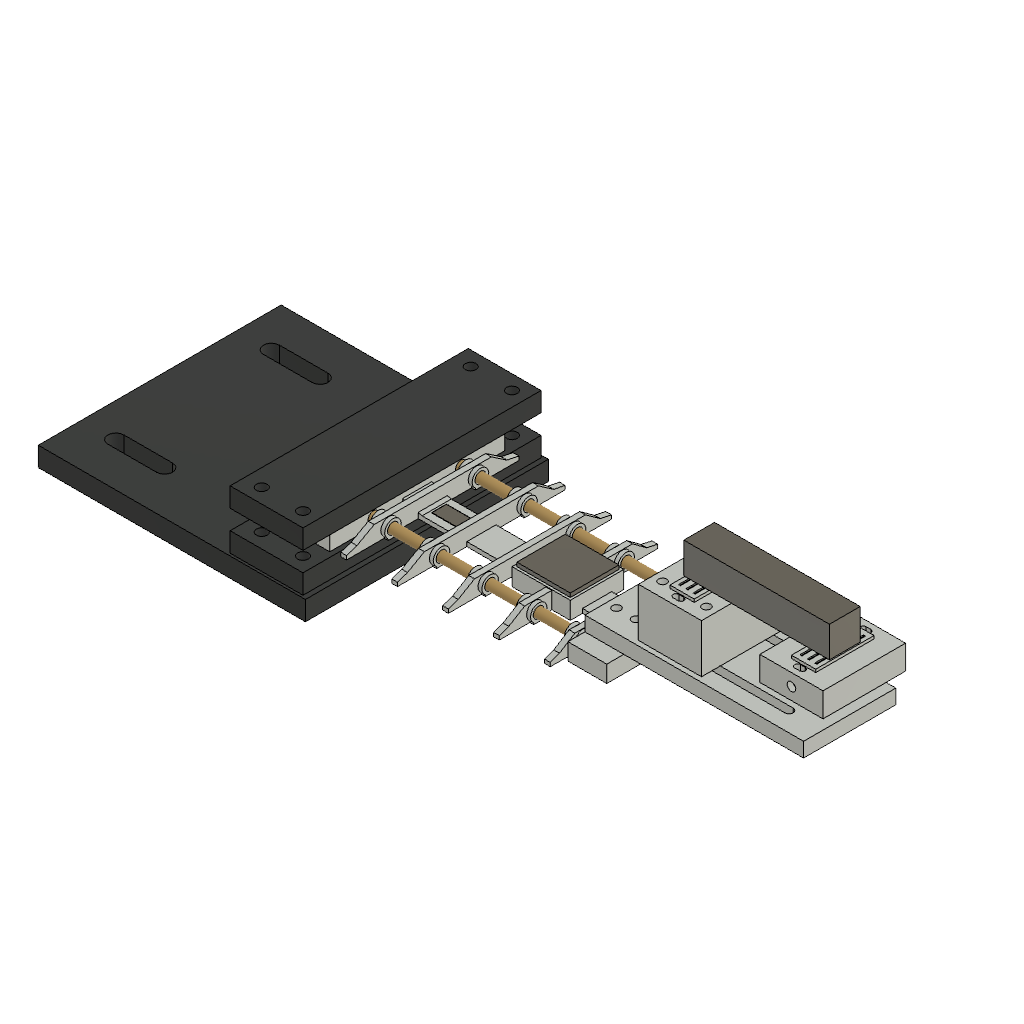
SkySafe_Assembly (Autodesk Fusion 360 design; units mm, degrees)
part number: 2026-10-10-16-37-15-513
part number: 2026-10-10-16-37-16-082
part number: 2026-10-10-16-37-18-375
part number: 2026-10-10-16-37-19-680
part number: 2026-10-10-16-37-20-182
part number: 2026-10-10-16-37-20-972
part number: 2026-10-10-16-37-22-516
part number: 2026-10-10-16-37-23-693
part number: 2026-10-10-16-37-41-112
Autodesk Fusion 360 part; units mm, degrees
(part 1 of 2)
sketch "Root tongue sketch" plane through (0, 0, 0) normal (0, 0, 1) x (1, 0, 0) in component "01 Flexible wing - short 4.5mm spar guides"
  line L0 (0, -36) -> (24, -36)
  line L1 (24, -36) -> (24, 36)
  line L2 (24, 36) -> (0, 36)
  line L3 (0, 36) -> (0, -36)
extrude "Root tongue" add sketch "Root tongue sketch" along normal blind 8 makes body 1 in component "01 Flexible wing - short 4.5mm spar guides"
sketch "Continuous flat flexing gauge strip sketch" plane through (0, 0, 0) normal (0, 0, 1) x (1, 0, 0) in component "01 Flexible wing - short 4.5mm spar guides"
  line L0 (23.95, -6) -> (128, -6)
  line L1 (128, -6) -> (128, 6)
  line L2 (128, 6) -> (23.95, 6)
  line L3 (23.95, 6) -> (23.95, -6)
extrude "Continuous flat flexing gauge strip" add sketch "Continuous flat flexing gauge strip sketch" along normal blind 1.8 bodies 1 in component "01 Flexible wing - short 4.5mm spar guides"
sketch "Root tapered strip shoulder sketch" plane through (0, 0, 0) normal (0, 1, 0) x (1, 0, 0) in component "01 Flexible wing - short 4.5mm spar guides"
  line L0 (23.95, 0) -> (32, 0)
  line L1 (32, 0) -> (32, -1.8)
  line L2 (32, -1.8) -> (23.95, -4)
  line L3 (23.95, -4) -> (23.95, 0)
extrude "Root tapered strip shoulder" add sketch "Root tapered strip shoulder sketch" along normal mid plane 12 bodies 1 in component "01 Flexible wing - short 4.5mm spar guides"
sketch "Tip tapered strip shoulder sketch" plane through (0, 0, 0) normal (0, 1, 0) x (1, 0, 0) in component "01 Flexible wing - short 4.5mm spar guides"
  line L0 (104, 0) -> (112.05, 0)
  line L1 (112.05, 0) -> (112.05, -6.95)
  line L2 (112.05, -6.95) -> (104, -1.8)
  line L3 (104, -1.8) -> (104, 0)
extrude "Tip tapered strip shoulder" add sketch "Tip tapered strip shoulder sketch" along normal mid plane 12 bodies 1 in component "01 Flexible wing - short 4.5mm spar guides"
ref_plane "WorkPlane1" through (28, 0, 0) normal (1, 0, 0) x (0, 1, 0) in component "01 Flexible wing - short 4.5mm spar guides"
sketch "Rib at 28 mm sketch" plane through (28, 0, 0) normal (1, 0, 0) x (0, 0, -1) in component "01 Flexible wing - short 4.5mm spar guides"
  line L0 (0, -35.4923) -> (0, 35.4923)
  line L1 (0, 35.4923) -> (-1.6, 35.4923)
  line L2 (-1.6, 35.4923) -> (-2.6, 30.5234)
  line L3 (-2.6, 30.5234) -> (-6.95, 24.1348)
  line L4 (-6.95, 24.1348) -> (-6.95, -24.1348)
  line L5 (-6.95, -24.1348) -> (-3, -31.2332)
  line L6 (-3, -31.2332) -> (-1.6, -35.4923)
  line L7 (-1.6, -35.4923) -> (0, -35.4923)
extrude "Rib at 28 mm" add sketch "Rib at 28 mm sketch" along normal blind 2.4 bodies 1 in component "01 Flexible wing - short 4.5mm spar guides"
ref_plane "WorkPlane2" through (26, 0, 0) normal (1, 0, 0) x (0, 1, 0) in component "01 Flexible wing - short 4.5mm spar guides"
sketch "front short guide at 28 mm sketch" plane through (26, 0, 0) normal (1, 0, 0) x (0, 0, -1) in component "01 Flexible wing - short 4.5mm spar guides"
  circle A0 centre (-3.4, -18) radius 3.4
extrude "front short guide at 28 mm" add sketch "front short guide at 28 mm sketch" along normal blind 6 bodies 1 in component "01 Flexible wing - short 4.5mm spar guides"
sketch "front guide print foot at 28 mm sketch" plane through (0, 0, 0) normal (0, 0, 1) x (1, 0, 0) in component "01 Flexible wing - short 4.5mm spar guides"
  line L0 (26, -20) -> (32, -20)
  line L1 (32, -20) -> (32, -16)
  line L2 (32, -16) -> (26, -16)
  line L3 (26, -16) -> (26, -20)
extrude "front guide print foot at 28 mm" add sketch "front guide print foot at 28 mm sketch" along normal blind 1.2 bodies 1 in component "01 Flexible wing - short 4.5mm spar guides"
ref_plane "WorkPlane3" through (26, 0, 0) normal (1, 0, 0) x (0, 1, 0) in component "01 Flexible wing - short 4.5mm spar guides"
sketch "rear short guide at 28 mm sketch" plane through (26, 0, 0) normal (1, 0, 0) x (0, 0, -1) in component "01 Flexible wing - short 4.5mm spar guides"
  circle A0 centre (-3.4, 18) radius 3.4
extrude "rear short guide at 28 mm" add sketch "rear short guide at 28 mm sketch" along normal blind 6 bodies 1 in component "01 Flexible wing - short 4.5mm spar guides"
sketch "rear guide print foot at 28 mm sketch" plane through (0, 0, 0) normal (0, 0, 1) x (1, 0, 0) in component "01 Flexible wing - short 4.5mm spar guides"
  line L0 (26, 16) -> (32, 16)
  line L1 (32, 16) -> (32, 20)
  line L2 (32, 20) -> (26, 20)
  line L3 (26, 20) -> (26, 16)
extrude "rear guide print foot at 28 mm" add sketch "rear guide print foot at 28 mm sketch" along normal blind 1.2 bodies 1 in component "01 Flexible wing - short 4.5mm spar guides"
ref_plane "WorkPlane4" through (48, 0, 0) normal (1, 0, 0) x (0, 1, 0) in component "01 Flexible wing - short 4.5mm spar guides"
sketch "Rib at 48 mm sketch" plane through (48, 0, 0) normal (1, 0, 0) x (0, 0, -1) in component "01 Flexible wing - short 4.5mm spar guides"
  line L0 (0, -34.5308) -> (0, 34.5308)
  line L1 (0, 34.5308) -> (-1.6, 34.5308)
  line L2 (-1.6, 34.5308) -> (-2.6, 29.6965)
  line L3 (-2.6, 29.6965) -> (-6.95, 23.4809)
  line L4 (-6.95, 23.4809) -> (-6.95, -23.4809)
  line L5 (-6.95, -23.4809) -> (-3, -30.3871)
  line L6 (-3, -30.3871) -> (-1.6, -34.5308)
  line L7 (-1.6, -34.5308) -> (0, -34.5308)
extrude "Rib at 48 mm" add sketch "Rib at 48 mm sketch" along normal blind 2.4 bodies 1 in component "01 Flexible wing - short 4.5mm spar guides"
ref_plane "WorkPlane5" through (46, 0, 0) normal (1, 0, 0) x (0, 1, 0) in component "01 Flexible wing - short 4.5mm spar guides"
sketch "front short guide at 48 mm sketch" plane through (46, 0, 0) normal (1, 0, 0) x (0, 0, -1) in component "01 Flexible wing - short 4.5mm spar guides"
  circle A0 centre (-3.4, -18) radius 3.4
extrude "front short guide at 48 mm" add sketch "front short guide at 48 mm sketch" along normal blind 6 bodies 1 in component "01 Flexible wing - short 4.5mm spar guides"
sketch "front guide print foot at 48 mm sketch" plane through (0, 0, 0) normal (0, 0, 1) x (1, 0, 0) in component "01 Flexible wing - short 4.5mm spar guides"
  line L0 (46, -20) -> (52, -20)
  line L1 (52, -20) -> (52, -16)
  line L2 (52, -16) -> (46, -16)
  line L3 (46, -16) -> (46, -20)
extrude "front guide print foot at 48 mm" add sketch "front guide print foot at 48 mm sketch" along normal blind 1.2 bodies 1 in component "01 Flexible wing - short 4.5mm spar guides"
ref_plane "WorkPlane6" through (46, 0, 0) normal (1, 0, 0) x (0, 1, 0) in component "01 Flexible wing - short 4.5mm spar guides"
sketch "rear short guide at 48 mm sketch" plane through (46, 0, 0) normal (1, 0, 0) x (0, 0, -1) in component "01 Flexible wing - short 4.5mm spar guides"
  circle A0 centre (-3.4, 18) radius 3.4
extrude "rear short guide at 48 mm" add sketch "rear short guide at 48 mm sketch" along normal blind 6 bodies 1 in component "01 Flexible wing - short 4.5mm spar guides"
sketch "rear guide print foot at 48 mm sketch" plane through (0, 0, 0) normal (0, 0, 1) x (1, 0, 0) in component "01 Flexible wing - short 4.5mm spar guides"
  line L0 (46, 16) -> (52, 16)
  line L1 (52, 16) -> (52, 20)
  line L2 (52, 20) -> (46, 20)
  line L3 (46, 20) -> (46, 16)
extrude "rear guide print foot at 48 mm" add sketch "rear guide print foot at 48 mm sketch" along normal blind 1.2 bodies 1 in component "01 Flexible wing - short 4.5mm spar guides"
ref_plane "WorkPlane7" through (68, 0, 0) normal (1, 0, 0) x (0, 1, 0) in component "01 Flexible wing - short 4.5mm spar guides"
sketch "Rib at 68 mm sketch" plane through (68, 0, 0) normal (1, 0, 0) x (0, 0, -1) in component "01 Flexible wing - short 4.5mm spar guides"
  line L0 (0, -33.5692) -> (0, 33.5692)
  line L1 (0, 33.5692) -> (-1.6, 33.5692)
  line L2 (-1.6, 33.5692) -> (-2.6, 28.8695)
  line L3 (-2.6, 28.8695) -> (-6.95, 22.8271)
  line L4 (-6.95, 22.8271) -> (-6.95, -22.8271)
  line L5 (-6.95, -22.8271) -> (-3, -29.5409)
  line L6 (-3, -29.5409) -> (-1.6, -33.5692)
  line L7 (-1.6, -33.5692) -> (0, -33.5692)
extrude "Rib at 68 mm" add sketch "Rib at 68 mm sketch" along normal blind 2.4 bodies 1 in component "01 Flexible wing - short 4.5mm spar guides"
ref_plane "WorkPlane8" through (66, 0, 0) normal (1, 0, 0) x (0, 1, 0) in component "01 Flexible wing - short 4.5mm spar guides"
sketch "front short guide at 68 mm sketch" plane through (66, 0, 0) normal (1, 0, 0) x (0, 0, -1) in component "01 Flexible wing - short 4.5mm spar guides"
  circle A0 centre (-3.4, -18) radius 3.4
extrude "front short guide at 68 mm" add sketch "front short guide at 68 mm sketch" along normal blind 6 bodies 1 in component "01 Flexible wing - short 4.5mm spar guides"
sketch "front guide print foot at 68 mm sketch" plane through (0, 0, 0) normal (0, 0, 1) x (1, 0, 0) in component "01 Flexible wing - short 4.5mm spar guides"
  line L0 (66, -20) -> (72, -20)
  line L1 (72, -20) -> (72, -16)
  line L2 (72, -16) -> (66, -16)
  line L3 (66, -16) -> (66, -20)
extrude "front guide print foot at 68 mm" add sketch "front guide print foot at 68 mm sketch" along normal blind 1.2 bodies 1 in component "01 Flexible wing - short 4.5mm spar guides"
ref_plane "WorkPlane9" through (66, 0, 0) normal (1, 0, 0) x (0, 1, 0) in component "01 Flexible wing - short 4.5mm spar guides"
sketch "rear short guide at 68 mm sketch" plane through (66, 0, 0) normal (1, 0, 0) x (0, 0, -1) in component "01 Flexible wing - short 4.5mm spar guides"
  circle A0 centre (-3.4, 18) radius 3.4
extrude "rear short guide at 68 mm" add sketch "rear short guide at 68 mm sketch" along normal blind 6 bodies 1 in component "01 Flexible wing - short 4.5mm spar guides"
sketch "rear guide print foot at 68 mm sketch" plane through (0, 0, 0) normal (0, 0, 1) x (1, 0, 0) in component "01 Flexible wing - short 4.5mm spar guides"
  line L0 (66, 16) -> (72, 16)
  line L1 (72, 16) -> (72, 20)
  line L2 (72, 20) -> (66, 20)
  line L3 (66, 20) -> (66, 16)
extrude "rear guide print foot at 68 mm" add sketch "rear guide print foot at 68 mm sketch" along normal blind 1.2 bodies 1 in component "01 Flexible wing - short 4.5mm spar guides"
ref_plane "WorkPlane10" through (88, 0, 0) normal (1, 0, 0) x (0, 1, 0) in component "01 Flexible wing - short 4.5mm spar guides"
sketch "Rib at 88 mm sketch" plane through (88, 0, 0) normal (1, 0, 0) x (0, 0, -1) in component "01 Flexible wing - short 4.5mm spar guides"
  line L0 (0, -32.6077) -> (0, 32.6077)
  line L1 (0, 32.6077) -> (-1.6, 32.6077)
  line L2 (-1.6, 32.6077) -> (-2.6, 28.0426)
  line L3 (-2.6, 28.0426) -> (-6.95, 22.1732)
  line L4 (-6.95, 22.1732) -> (-6.95, -22.1732)
  line L5 (-6.95, -22.1732) -> (-3, -28.6948)
  line L6 (-3, -28.6948) -> (-1.6, -32.6077)
  line L7 (-1.6, -32.6077) -> (0, -32.6077)
extrude "Rib at 88 mm" add sketch "Rib at 88 mm sketch" along normal blind 2.4 bodies 1 in component "01 Flexible wing - short 4.5mm spar guides"
ref_plane "WorkPlane11" through (86, 0, 0) normal (1, 0, 0) x (0, 1, 0) in component "01 Flexible wing - short 4.5mm spar guides"
sketch "front short guide at 88 mm sketch" plane through (86, 0, 0) normal (1, 0, 0) x (0, 0, -1) in component "01 Flexible wing - short 4.5mm spar guides"
  circle A0 centre (-3.4, -18) radius 3.4
extrude "front short guide at 88 mm" add sketch "front short guide at 88 mm sketch" along normal blind 6 bodies 1 in component "01 Flexible wing - short 4.5mm spar guides"
sketch "front guide print foot at 88 mm sketch" plane through (0, 0, 0) normal (0, 0, 1) x (1, 0, 0) in component "01 Flexible wing - short 4.5mm spar guides"
  line L0 (86, -20) -> (92, -20)
  line L1 (92, -20) -> (92, -16)
  line L2 (92, -16) -> (86, -16)
  line L3 (86, -16) -> (86, -20)
extrude "front guide print foot at 88 mm" add sketch "front guide print foot at 88 mm sketch" along normal blind 1.2 bodies 1 in component "01 Flexible wing - short 4.5mm spar guides"
ref_plane "WorkPlane12" through (86, 0, 0) normal (1, 0, 0) x (0, 1, 0) in component "01 Flexible wing - short 4.5mm spar guides"
sketch "rear short guide at 88 mm sketch" plane through (86, 0, 0) normal (1, 0, 0) x (0, 0, -1) in component "01 Flexible wing - short 4.5mm spar guides"
  circle A0 centre (-3.4, 18) radius 3.4
extrude "rear short guide at 88 mm" add sketch "rear short guide at 88 mm sketch" along normal blind 6 bodies 1 in component "01 Flexible wing - short 4.5mm spar guides"
sketch "rear guide print foot at 88 mm sketch" plane through (0, 0, 0) normal (0, 0, 1) x (1, 0, 0) in component "01 Flexible wing - short 4.5mm spar guides"
  line L0 (86, 16) -> (92, 16)
  line L1 (92, 16) -> (92, 20)
  line L2 (92, 20) -> (86, 20)
  line L3 (86, 20) -> (86, 16)
extrude "rear guide print foot at 88 mm" add sketch "rear guide print foot at 88 mm sketch" along normal blind 1.2 bodies 1 in component "01 Flexible wing - short 4.5mm spar guides"
ref_plane "WorkPlane13" through (108, 0, 0) normal (1, 0, 0) x (0, 1, 0) in component "01 Flexible wing - short 4.5mm spar guides"
sketch "Rib at 108 mm sketch" plane through (108, 0, 0) normal (1, 0, 0) x (0, 0, -1) in component "01 Flexible wing - short 4.5mm spar guides"
  line L0 (0, -31.6462) -> (0, 31.6462)
  line L1 (0, 31.6462) -> (-1.6, 31.6462)
  line L2 (-1.6, 31.6462) -> (-2.6, 27.2157)
  line L3 (-2.6, 27.2157) -> (-6.95, 21.5194)
  line L4 (-6.95, 21.5194) -> (-6.95, -21.5194)
  line L5 (-6.95, -21.5194) -> (-3, -27.8486)
  line L6 (-3, -27.8486) -> (-1.6, -31.6462)
  line L7 (-1.6, -31.6462) -> (0, -31.6462)
extrude "Rib at 108 mm" add sketch "Rib at 108 mm sketch" along normal blind 2.4 bodies 1 in component "01 Flexible wing - short 4.5mm spar guides"
ref_plane "WorkPlane14" through (106, 0, 0) normal (1, 0, 0) x (0, 1, 0) in component "01 Flexible wing - short 4.5mm spar guides"
sketch "front short guide at 108 mm sketch" plane through (106, 0, 0) normal (1, 0, 0) x (0, 0, -1) in component "01 Flexible wing - short 4.5mm spar guides"
  circle A0 centre (-3.4, -18) radius 3.4
extrude "front short guide at 108 mm" add sketch "front short guide at 108 mm sketch" along normal blind 6 bodies 1 in component "01 Flexible wing - short 4.5mm spar guides"
sketch "front guide print foot at 108 mm sketch" plane through (0, 0, 0) normal (0, 0, 1) x (1, 0, 0) in component "01 Flexible wing - short 4.5mm spar guides"
  line L0 (106, -20) -> (112, -20)
  line L1 (112, -20) -> (112, -16)
  line L2 (112, -16) -> (106, -16)
  line L3 (106, -16) -> (106, -20)
extrude "front guide print foot at 108 mm" add sketch "front guide print foot at 108 mm sketch" along normal blind 1.2 bodies 1 in component "01 Flexible wing - short 4.5mm spar guides"
ref_plane "WorkPlane15" through (106, 0, 0) normal (1, 0, 0) x (0, 1, 0) in component "01 Flexible wing - short 4.5mm spar guides"
sketch "rear short guide at 108 mm sketch" plane through (106, 0, 0) normal (1, 0, 0) x (0, 0, -1) in component "01 Flexible wing - short 4.5mm spar guides"
  circle A0 centre (-3.4, 18) radius 3.4
extrude "rear short guide at 108 mm" add sketch "rear short guide at 108 mm sketch" along normal blind 6 bodies 1 in component "01 Flexible wing - short 4.5mm spar guides"
sketch "rear guide print foot at 108 mm sketch" plane through (0, 0, 0) normal (0, 0, 1) x (1, 0, 0) in component "01 Flexible wing - short 4.5mm spar guides"
  line L0 (106, 16) -> (112, 16)
  line L1 (112, 16) -> (112, 20)
  line L2 (112, 20) -> (106, 20)
  line L3 (106, 20) -> (106, 16)
extrude "rear guide print foot at 108 mm" add sketch "rear guide print foot at 108 mm sketch" along normal blind 1.2 bodies 1 in component "01 Flexible wing - short 4.5mm spar guides"
sketch "Tip load landing sketch" plane through (0, 0, 0) normal (0, 0, 1) x (1, 0, 0) in component "01 Flexible wing - short 4.5mm spar guides"
  line L0 (112, -26) -> (128, -26)
  line L1 (128, -26) -> (128, 26)
  line L2 (128, 26) -> (112, 26)
  line L3 (112, 26) -> (112, -26)
extrude "Tip load landing" add sketch "Tip load landing sketch" along normal blind 6.95 bodies 1 in component "01 Flexible wing - short 4.5mm spar guides"
sketch "MPU strap landing sketch" plane through (0, 0, 0) normal (0, 0, 1) x (1, 0, 0) in component "01 Flexible wing - short 4.5mm spar guides"
  line L0 (74, -11) -> (98, -11)
  line L1 (98, -11) -> (98, 11)
  line L2 (98, 11) -> (74, 11)
  line L3 (74, 11) -> (74, -11)
extrude "MPU strap landing" add sketch "MPU strap landing sketch" along normal blind 7.2 bodies 1 in component "01 Flexible wing - short 4.5mm spar guides"
ref_plane "WorkPlane16" through (-0.05, 0, 0) normal (1, 0, 0) x (0, 1, 0) in component "01 Flexible wing - short 4.5mm spar guides"
sketch "front 4mm bamboo passage sketch" plane through (-0.05, 0, 0) normal (1, 0, 0) x (0, 0, -1) in component "01 Flexible wing - short 4.5mm spar guides"
  circle A0 centre (-3.4, -18) radius 2.25
  dimension "d103" = 4.5
  measures "d103" diameter of A0
extrude "front 4mm bamboo passage" cut sketch "front 4mm bamboo passage sketch" along normal blind 126.05 bodies 1 in component "01 Flexible wing - short 4.5mm spar guides"
ref_plane "WorkPlane17" through (-0.05, 0, 0) normal (1, 0, 0) x (0, 1, 0) in component "01 Flexible wing - short 4.5mm spar guides"
sketch "rear 4mm bamboo passage sketch" plane through (-0.05, 0, 0) normal (1, 0, 0) x (0, 0, -1) in component "01 Flexible wing - short 4.5mm spar guides"
  circle A0 centre (-3.4, 18) radius 2.25
  dimension "d108" = 4.5
  measures "d108" diameter of A0
extrude "rear 4mm bamboo passage" cut sketch "rear 4mm bamboo passage sketch" along normal blind 126.05 bodies 1 in component "01 Flexible wing - short 4.5mm spar guides"
ref_plane "WorkPlane18" through (0, 0, -0.05) normal (0, 0, 1) x (1, 0, 0) in component "01 Flexible wing - short 4.5mm spar guides"
sketch "Root registration -8 sketch" plane through (0, 0, -0.05) normal (0, 0, 1) x (1, 0, 0) in component "01 Flexible wing - short 4.5mm spar guides"
  circle A0 centre (8, -8) radius 1.7
  dimension "d113" = 3.4
  measures "d113" diameter of A0
extrude "Root registration -8" cut sketch "Root registration -8 sketch" along normal blind 8.1 bodies 1 in component "01 Flexible wing - short 4.5mm spar guides"
ref_plane "WorkPlane19" through (0, 0, -0.05) normal (0, 0, 1) x (1, 0, 0) in component "01 Flexible wing - short 4.5mm spar guides"
sketch "Root registration 8 sketch" plane through (0, 0, -0.05) normal (0, 0, 1) x (1, 0, 0) in component "01 Flexible wing - short 4.5mm spar guides"
  circle A0 centre (8, 8) radius 1.7
  dimension "d118" = 3.4
  measures "d118" diameter of A0
extrude "Root registration 8" cut sketch "Root registration 8 sketch" along normal blind 8.1 bodies 1 in component "01 Flexible wing - short 4.5mm spar guides"
ref_plane "WorkPlane20" through (0, 0, -0.05) normal (0, 0, 1) x (1, 0, 0) in component "01 Flexible wing - short 4.5mm spar guides"
sketch "Tip bolt 116 -10 sketch" plane through (0, 0, -0.05) normal (0, 0, 1) x (1, 0, 0) in component "01 Flexible wing - short 4.5mm spar guides"
  circle A0 centre (116, -10) radius 1.7
  dimension "d123" = 3.4
  measures "d123" diameter of A0
extrude "Tip bolt 116 -10" cut sketch "Tip bolt 116 -10 sketch" along normal blind 7.05 bodies 1 in component "01 Flexible wing - short 4.5mm spar guides"
ref_plane "WorkPlane21" through (0, 0, -0.05) normal (0, 0, 1) x (1, 0, 0) in component "01 Flexible wing - short 4.5mm spar guides"
sketch "Tip bolt 116 10 sketch" plane through (0, 0, -0.05) normal (0, 0, 1) x (1, 0, 0) in component "01 Flexible wing - short 4.5mm spar guides"
  circle A0 centre (116, 10) radius 1.7
  dimension "d128" = 3.4
  measures "d128" diameter of A0
extrude "Tip bolt 116 10" cut sketch "Tip bolt 116 10 sketch" along normal blind 7.05 bodies 1 in component "01 Flexible wing - short 4.5mm spar guides"
ref_plane "WorkPlane22" through (0, 0, -0.05) normal (0, 0, 1) x (1, 0, 0) in component "01 Flexible wing - short 4.5mm spar guides"
sketch "Tip bolt 124 -10 sketch" plane through (0, 0, -0.05) normal (0, 0, 1) x (1, 0, 0) in component "01 Flexible wing - short 4.5mm spar guides"
  circle A0 centre (124, -10) radius 1.7
  dimension "d133" = 3.4
  measures "d133" diameter of A0
extrude "Tip bolt 124 -10" cut sketch "Tip bolt 124 -10 sketch" along normal blind 7.05 bodies 1 in component "01 Flexible wing - short 4.5mm spar guides"
ref_plane "WorkPlane23" through (0, 0, -0.05) normal (0, 0, 1) x (1, 0, 0) in component "01 Flexible wing - short 4.5mm spar guides"
sketch "Tip bolt 124 10 sketch" plane through (0, 0, -0.05) normal (0, 0, 1) x (1, 0, 0) in component "01 Flexible wing - short 4.5mm spar guides"
  circle A0 centre (124, 10) radius 1.7
  dimension "d138" = 3.4
  measures "d138" diameter of A0
extrude "Tip bolt 124 10" cut sketch "Tip bolt 124 10 sketch" along normal blind 7.05 bodies 1 in component "01 Flexible wing - short 4.5mm spar guides"
ref_plane "WorkPlane24" through (0, 0, -0.05) normal (0, 0, 1) x (1, 0, 0) in component "01 Flexible wing - short 4.5mm spar guides"
sketch "Board tie 78 -7 sketch" plane through (0, 0, -0.05) normal (0, 0, 1) x (1, 0, 0) in component "01 Flexible wing - short 4.5mm spar guides"
  arc A0 (77.5, -5.9) -> (77.5, -8.1) centre (77.5, -7) ccw
  line L0 (77.5, -5.9) -> (78.5, -5.9)
  arc A1 (78.5, -8.1) -> (78.5, -5.9) centre (78.5, -7) ccw
  line L1 (78.5, -8.1) -> (77.5, -8.1)
extrude "Board tie 78 -7" cut sketch "Board tie 78 -7 sketch" along normal blind 7.3 bodies 1 in component "01 Flexible wing - short 4.5mm spar guides"
ref_plane "WorkPlane25" through (0, 0, -0.05) normal (0, 0, 1) x (1, 0, 0) in component "01 Flexible wing - short 4.5mm spar guides"
sketch "Board tie 78 7 sketch" plane through (0, 0, -0.05) normal (0, 0, 1) x (1, 0, 0) in component "01 Flexible wing - short 4.5mm spar guides"
  arc A0 (77.5, 8.1) -> (77.5, 5.9) centre (77.5, 7) ccw
  line L0 (77.5, 8.1) -> (78.5, 8.1)
  arc A1 (78.5, 5.9) -> (78.5, 8.1) centre (78.5, 7) ccw
  line L1 (78.5, 5.9) -> (77.5, 5.9)
extrude "Board tie 78 7" cut sketch "Board tie 78 7 sketch" along normal blind 7.3 bodies 1 in component "01 Flexible wing - short 4.5mm spar guides"
ref_plane "WorkPlane26" through (0, 0, -0.05) normal (0, 0, 1) x (1, 0, 0) in component "01 Flexible wing - short 4.5mm spar guides"
sketch "Board tie 94 -7 sketch" plane through (0, 0, -0.05) normal (0, 0, 1) x (1, 0, 0) in component "01 Flexible wing - short 4.5mm spar guides"
  arc A0 (93.5, -5.9) -> (93.5, -8.1) centre (93.5, -7) ccw
  line L0 (93.5, -5.9) -> (94.5, -5.9)
  arc A1 (94.5, -8.1) -> (94.5, -5.9) centre (94.5, -7) ccw
  line L1 (94.5, -8.1) -> (93.5, -8.1)
extrude "Board tie 94 -7" cut sketch "Board tie 94 -7 sketch" along normal blind 7.3 bodies 1 in component "01 Flexible wing - short 4.5mm spar guides"
ref_plane "WorkPlane27" through (0, 0, -0.05) normal (0, 0, 1) x (1, 0, 0) in component "01 Flexible wing - short 4.5mm spar guides"
sketch "Board tie 94 7 sketch" plane through (0, 0, -0.05) normal (0, 0, 1) x (1, 0, 0) in component "01 Flexible wing - short 4.5mm spar guides"
  arc A0 (93.5, 8.1) -> (93.5, 5.9) centre (93.5, 7) ccw
  line L0 (93.5, 8.1) -> (94.5, 8.1)
  arc A1 (94.5, 5.9) -> (94.5, 8.1) centre (94.5, 7) ccw
  line L1 (94.5, 5.9) -> (93.5, 5.9)
extrude "Board tie 94 7" cut sketch "Board tie 94 7 sketch" along normal blind 7.3 bodies 1 in component "01 Flexible wing - short 4.5mm spar guides"
sketch "Bench mounting plate sketch" plane through (0, 0, 0) normal (0, 0, 1) x (1, 0, 0) in component "02 Root base - bench clamp"
  line L0 (-82, -50) -> (28, -50)
  line L1 (28, -50) -> (28, 50)
  line L2 (28, 50) -> (-82, 50)
  line L3 (-82, 50) -> (-82, -50)
extrude "Bench mounting plate" add sketch "Bench mounting plate sketch" along normal blind 8 separate body makes body 2 in component "02 Root base - bench clamp"
ref_plane "WorkPlane1" through (0, 0, 8) normal (0, 0, 1) x (1, 0, 0) in component "02 Root base - bench clamp"
sketch "Lower root jaw sketch" plane through (0, 0, 8) normal (0, 0, 1) x (1, 0, 0) in component "02 Root base - bench clamp"
  line L0 (-4, -49) -> (26, -49)
  line L1 (26, -49) -> (26, 49)
  line L2 (26, 49) -> (-4, 49)
  line L3 (-4, 49) -> (-4, -49)
extrude "Lower root jaw" add sketch "Lower root jaw sketch" along normal blind 8 bodies 2 in component "02 Root base - bench clamp"
ref_plane "WorkPlane2" through (0, 0, 15.95) normal (0, 0, 1) x (1, 0, 0) in component "02 Root base - bench clamp"
sketch "Root pin -8 sketch" plane through (0, 0, 15.95) normal (0, 0, 1) x (1, 0, 0) in component "02 Root base - bench clamp"
  circle A0 centre (8, -8) radius 1.5
extrude "Root pin -8" add sketch "Root pin -8 sketch" along normal blind 2.05 bodies 2 in component "02 Root base - bench clamp"
ref_plane "WorkPlane3" through (0, 0, 15.95) normal (0, 0, 1) x (1, 0, 0) in component "02 Root base - bench clamp"
sketch "Root pin 8 sketch" plane through (0, 0, 15.95) normal (0, 0, 1) x (1, 0, 0) in component "02 Root base - bench clamp"
  circle A0 centre (8, 8) radius 1.5
extrude "Root pin 8" add sketch "Root pin 8 sketch" along normal blind 2.05 bodies 2 in component "02 Root base - bench clamp"
ref_plane "WorkPlane4" through (0, 0, -0.05) normal (0, 0, 1) x (1, 0, 0) in component "02 Root base - bench clamp"
sketch "Jaw bolt 3 -43 sketch" plane through (0, 0, -0.05) normal (0, 0, 1) x (1, 0, 0) in component "02 Root base - bench clamp"
  circle A0 centre (3, -43) radius 2.2
  dimension "d173" = 4.4
  measures "d173" diameter of A0
extrude "Jaw bolt 3 -43" cut sketch "Jaw bolt 3 -43 sketch" along normal blind 16.1 bodies 2 in component "02 Root base - bench clamp"
ref_plane "WorkPlane5" through (0, 0, -0.05) normal (0, 0, 1) x (1, 0, 0) in component "02 Root base - bench clamp"
sketch "Nut pocket 3 -43 sketch" plane through (0, 0, -0.05) normal (0, 0, 1) x (1, 0, 0) in component "02 Root base - bench clamp"
  line L0 (6.55, -40.9504) -> (3, -38.9008)
  line L1 (3, -38.9008) -> (-0.55, -40.9504)
  line L2 (-0.55, -40.9504) -> (-0.55, -45.0496)
  line L3 (-0.55, -45.0496) -> (3, -47.0992)
  line L4 (3, -47.0992) -> (6.55, -45.0496)
  line L5 (6.55, -45.0496) -> (6.55, -40.9504)
extrude "Nut pocket 3 -43" cut sketch "Nut pocket 3 -43 sketch" along normal blind 3.35 bodies 2 in component "02 Root base - bench clamp"
ref_plane "WorkPlane6" through (0, 0, -0.05) normal (0, 0, 1) x (1, 0, 0) in component "02 Root base - bench clamp"
sketch "Jaw bolt 3 43 sketch" plane through (0, 0, -0.05) normal (0, 0, 1) x (1, 0, 0) in component "02 Root base - bench clamp"
  circle A0 centre (3, 43) radius 2.2
  dimension "d182" = 4.4
  measures "d182" diameter of A0
extrude "Jaw bolt 3 43" cut sketch "Jaw bolt 3 43 sketch" along normal blind 16.1 bodies 2 in component "02 Root base - bench clamp"
ref_plane "WorkPlane7" through (0, 0, -0.05) normal (0, 0, 1) x (1, 0, 0) in component "02 Root base - bench clamp"
sketch "Nut pocket 3 43 sketch" plane through (0, 0, -0.05) normal (0, 0, 1) x (1, 0, 0) in component "02 Root base - bench clamp"
  line L0 (6.55, 45.0496) -> (3, 47.0992)
  line L1 (3, 47.0992) -> (-0.55, 45.0496)
  line L2 (-0.55, 45.0496) -> (-0.55, 40.9504)
  line L3 (-0.55, 40.9504) -> (3, 38.9008)
  line L4 (3, 38.9008) -> (6.55, 40.9504)
  line L5 (6.55, 40.9504) -> (6.55, 45.0496)
extrude "Nut pocket 3 43" cut sketch "Nut pocket 3 43 sketch" along normal blind 3.35 bodies 2 in component "02 Root base - bench clamp"
ref_plane "WorkPlane8" through (0, 0, -0.05) normal (0, 0, 1) x (1, 0, 0) in component "02 Root base - bench clamp"
sketch "Jaw bolt 20 -43 sketch" plane through (0, 0, -0.05) normal (0, 0, 1) x (1, 0, 0) in component "02 Root base - bench clamp"
  circle A0 centre (20, -43) radius 2.2
  dimension "d191" = 4.4
  measures "d191" diameter of A0
extrude "Jaw bolt 20 -43" cut sketch "Jaw bolt 20 -43 sketch" along normal blind 16.1 bodies 2 in component "02 Root base - bench clamp"
ref_plane "WorkPlane9" through (0, 0, -0.05) normal (0, 0, 1) x (1, 0, 0) in component "02 Root base - bench clamp"
sketch "Nut pocket 20 -43 sketch" plane through (0, 0, -0.05) normal (0, 0, 1) x (1, 0, 0) in component "02 Root base - bench clamp"
  line L0 (23.55, -40.9504) -> (20, -38.9008)
  line L1 (20, -38.9008) -> (16.45, -40.9504)
  line L2 (16.45, -40.9504) -> (16.45, -45.0496)
  line L3 (16.45, -45.0496) -> (20, -47.0992)
  line L4 (20, -47.0992) -> (23.55, -45.0496)
  line L5 (23.55, -45.0496) -> (23.55, -40.9504)
extrude "Nut pocket 20 -43" cut sketch "Nut pocket 20 -43 sketch" along normal blind 3.35 bodies 2 in component "02 Root base - bench clamp"
ref_plane "WorkPlane10" through (0, 0, -0.05) normal (0, 0, 1) x (1, 0, 0) in component "02 Root base - bench clamp"
sketch "Jaw bolt 20 43 sketch" plane through (0, 0, -0.05) normal (0, 0, 1) x (1, 0, 0) in component "02 Root base - bench clamp"
  circle A0 centre (20, 43) radius 2.2
  dimension "d200" = 4.4
  measures "d200" diameter of A0
extrude "Jaw bolt 20 43" cut sketch "Jaw bolt 20 43 sketch" along normal blind 16.1 bodies 2 in component "02 Root base - bench clamp"
ref_plane "WorkPlane11" through (0, 0, -0.05) normal (0, 0, 1) x (1, 0, 0) in component "02 Root base - bench clamp"
sketch "Nut pocket 20 43 sketch" plane through (0, 0, -0.05) normal (0, 0, 1) x (1, 0, 0) in component "02 Root base - bench clamp"
  line L0 (23.55, 45.0496) -> (20, 47.0992)
  line L1 (20, 47.0992) -> (16.45, 45.0496)
  line L2 (16.45, 45.0496) -> (16.45, 40.9504)
  line L3 (16.45, 40.9504) -> (20, 38.9008)
  line L4 (20, 38.9008) -> (23.55, 40.9504)
  line L5 (23.55, 40.9504) -> (23.55, 45.0496)
extrude "Nut pocket 20 43" cut sketch "Nut pocket 20 43 sketch" along normal blind 3.35 bodies 2 in component "02 Root base - bench clamp"
ref_plane "WorkPlane12" through (0, 0, -0.05) normal (0, 0, 1) x (1, 0, 0) in component "02 Root base - bench clamp"
sketch "Bench slot -32 sketch" plane through (0, 0, -0.05) normal (0, 0, 1) x (1, 0, 0) in component "02 Root base - bench clamp"
  arc A0 (-68, -28.7) -> (-68, -35.3) centre (-68, -32) ccw
  line L0 (-68, -28.7) -> (-48, -28.7)
  arc A1 (-48, -35.3) -> (-48, -28.7) centre (-48, -32) ccw
  line L1 (-48, -35.3) -> (-68, -35.3)
extrude "Bench slot -32" cut sketch "Bench slot -32 sketch" along normal blind 8.1 bodies 2 in component "02 Root base - bench clamp"
ref_plane "WorkPlane13" through (0, 0, -0.05) normal (0, 0, 1) x (1, 0, 0) in component "02 Root base - bench clamp"
sketch "Bench slot 32 sketch" plane through (0, 0, -0.05) normal (0, 0, 1) x (1, 0, 0) in component "02 Root base - bench clamp"
  arc A0 (-68, 35.3) -> (-68, 28.7) centre (-68, 32) ccw
  line L0 (-68, 35.3) -> (-48, 35.3)
  arc A1 (-48, 28.7) -> (-48, 35.3) centre (-48, 32) ccw
  line L1 (-48, 28.7) -> (-68, 28.7)
extrude "Bench slot 32" cut sketch "Bench slot 32 sketch" along normal blind 8.1 bodies 2 in component "02 Root base - bench clamp"
sketch "Upper root jaw sketch" plane through (0, 0, 0) normal (0, 0, 1) x (1, 0, 0) in component "03 Root cap"
  line L0 (-4, -49) -> (26, -49)
  line L1 (26, -49) -> (26, 49)
  line L2 (26, 49) -> (-4, 49)
  line L3 (-4, 49) -> (-4, -49)
extrude "Upper root jaw" add sketch "Upper root jaw sketch" along normal blind 8 separate body makes body 3 in component "03 Root cap"
ref_plane "WorkPlane1" through (0, 0, -0.05) normal (0, 0, 1) x (1, 0, 0) in component "03 Root cap"
sketch "Cap bolt 3 -43 sketch" plane through (0, 0, -0.05) normal (0, 0, 1) x (1, 0, 0) in component "03 Root cap"
  circle A0 centre (3, -43) radius 2.2
  dimension "d219" = 4.4
  measures "d219" diameter of A0
extrude "Cap bolt 3 -43" cut sketch "Cap bolt 3 -43 sketch" along normal blind 8.1 bodies 3 in component "03 Root cap"
ref_plane "WorkPlane2" through (0, 0, -0.05) normal (0, 0, 1) x (1, 0, 0) in component "03 Root cap"
sketch "Cap bolt 3 43 sketch" plane through (0, 0, -0.05) normal (0, 0, 1) x (1, 0, 0) in component "03 Root cap"
  circle A0 centre (3, 43) radius 2.2
  dimension "d224" = 4.4
  measures "d224" diameter of A0
extrude "Cap bolt 3 43" cut sketch "Cap bolt 3 43 sketch" along normal blind 8.1 bodies 3 in component "03 Root cap"
ref_plane "WorkPlane3" through (0, 0, -0.05) normal (0, 0, 1) x (1, 0, 0) in component "03 Root cap"
sketch "Cap bolt 20 -43 sketch" plane through (0, 0, -0.05) normal (0, 0, 1) x (1, 0, 0) in component "03 Root cap"
  circle A0 centre (20, -43) radius 2.2
  dimension "d229" = 4.4
  measures "d229" diameter of A0
extrude "Cap bolt 20 -43" cut sketch "Cap bolt 20 -43 sketch" along normal blind 8.1 bodies 3 in component "03 Root cap"
ref_plane "WorkPlane4" through (0, 0, -0.05) normal (0, 0, 1) x (1, 0, 0) in component "03 Root cap"
sketch "Cap bolt 20 43 sketch" plane through (0, 0, -0.05) normal (0, 0, 1) x (1, 0, 0) in component "03 Root cap"
  circle A0 centre (20, 43) radius 2.2
  dimension "d234" = 4.4
  measures "d234" diameter of A0
extrude "Cap bolt 20 43" cut sketch "Cap bolt 20 43 sketch" along normal blind 8.1 bodies 3 in component "03 Root cap"
sketch "Adapter plate sketch" plane through (0, 0, 0) normal (0, 0, 1) x (1, 0, 0) in component "04 Tip adapter - adjustable glue mount rails"
  line L0 (0, -19) -> (90, -19)
  line L1 (90, -19) -> (90, 19)
  line L2 (90, 19) -> (0, 19)
  line L3 (0, 19) -> (0, -19)
extrude "Adapter plate" add sketch "Adapter plate sketch" along normal blind 6 separate body makes body 4 in component "04 Tip adapter - adjustable glue mount rails"
ref_plane "WorkPlane1" through (0, 0, -0.05) normal (0, 0, 1) x (1, 0, 0) in component "04 Tip adapter - adjustable glue mount rails"
sketch "Wing adapter bolt 4 -10 sketch" plane through (0, 0, -0.05) normal (0, 0, 1) x (1, 0, 0) in component "04 Tip adapter - adjustable glue mount rails"
  circle A0 centre (4, -10) radius 1.7
  dimension "d241" = 3.4
  measures "d241" diameter of A0
extrude "Wing adapter bolt 4 -10" cut sketch "Wing adapter bolt 4 -10 sketch" along normal blind 6.1 bodies 4 in component "04 Tip adapter - adjustable glue mount rails"
ref_plane "WorkPlane2" through (0, 0, -0.05) normal (0, 0, 1) x (1, 0, 0) in component "04 Tip adapter - adjustable glue mount rails"
sketch "Wing adapter bolt 4 10 sketch" plane through (0, 0, -0.05) normal (0, 0, 1) x (1, 0, 0) in component "04 Tip adapter - adjustable glue mount rails"
  circle A0 centre (4, 10) radius 1.7
  dimension "d246" = 3.4
  measures "d246" diameter of A0
extrude "Wing adapter bolt 4 10" cut sketch "Wing adapter bolt 4 10 sketch" along normal blind 6.1 bodies 4 in component "04 Tip adapter - adjustable glue mount rails"
ref_plane "WorkPlane3" through (0, 0, -0.05) normal (0, 0, 1) x (1, 0, 0) in component "04 Tip adapter - adjustable glue mount rails"
sketch "Wing adapter bolt 12 -10 sketch" plane through (0, 0, -0.05) normal (0, 0, 1) x (1, 0, 0) in component "04 Tip adapter - adjustable glue mount rails"
  circle A0 centre (12, -10) radius 1.7
  dimension "d251" = 3.4
  measures "d251" diameter of A0
extrude "Wing adapter bolt 12 -10" cut sketch "Wing adapter bolt 12 -10 sketch" along normal blind 6.1 bodies 4 in component "04 Tip adapter - adjustable glue mount rails"
ref_plane "WorkPlane4" through (0, 0, -0.05) normal (0, 0, 1) x (1, 0, 0) in component "04 Tip adapter - adjustable glue mount rails"
sketch "Wing adapter bolt 12 10 sketch" plane through (0, 0, -0.05) normal (0, 0, 1) x (1, 0, 0) in component "04 Tip adapter - adjustable glue mount rails"
  circle A0 centre (12, 10) radius 1.7
  dimension "d256" = 3.4
  measures "d256" diameter of A0
extrude "Wing adapter bolt 12 10" cut sketch "Wing adapter bolt 12 10 sketch" along normal blind 6.1 bodies 4 in component "04 Tip adapter - adjustable glue mount rails"
ref_plane "WorkPlane5" through (0, 0, -0.05) normal (0, 0, 1) x (1, 0, 0) in component "04 Tip adapter - adjustable glue mount rails"
sketch "Fixed mount sliding rail -11 sketch" plane through (0, 0, -0.05) normal (0, 0, 1) x (1, 0, 0) in component "04 Tip adapter - adjustable glue mount rails"
  arc A0 (24, -9.3) -> (24, -12.7) centre (24, -11) ccw
  line L0 (24, -9.3) -> (76, -9.3)
  arc A1 (76, -12.7) -> (76, -9.3) centre (76, -11) ccw
  line L1 (76, -12.7) -> (24, -12.7)
extrude "Fixed mount sliding rail -11" cut sketch "Fixed mount sliding rail -11 sketch" along normal blind 6.1 bodies 4 in component "04 Tip adapter - adjustable glue mount rails"
ref_plane "WorkPlane6" through (0, 0, -0.05) normal (0, 0, 1) x (1, 0, 0) in component "04 Tip adapter - adjustable glue mount rails"
sketch "Fixed mount sliding rail 11 sketch" plane through (0, 0, -0.05) normal (0, 0, 1) x (1, 0, 0) in component "04 Tip adapter - adjustable glue mount rails"
  arc A0 (24, 12.7) -> (24, 9.3) centre (24, 11) ccw
  line L0 (24, 12.7) -> (76, 12.7)
  arc A1 (76, 9.3) -> (76, 12.7) centre (76, 11) ccw
  line L1 (76, 9.3) -> (24, 9.3)
extrude "Fixed mount sliding rail 11" cut sketch "Fixed mount sliding rail 11 sketch" along normal blind 6.1 bodies 4 in component "04 Tip adapter - adjustable glue mount rails"
sketch "Glue carrier body sketch" plane through (0, 0, 0) normal (0, 0, 1) x (1, 0, 0) in component "05 Fixed end glue pedestal"
  line L0 (-13, -17) -> (13, -17)
  line L1 (13, -17) -> (13, 17)
  line L2 (13, 17) -> (-13, 17)
  line L3 (-13, 17) -> (-13, -17)
extrude "Glue carrier body" add sketch "Glue carrier body sketch" along normal blind 20 separate body makes body 5 in component "05 Fixed end glue pedestal"
ref_plane "WorkPlane1" through (0, 0, 19.95) normal (0, 0, 1) x (1, 0, 0) in component "05 Fixed end glue pedestal"
sketch "END ONLY 10x24 glue landing sketch" plane through (0, 0, 19.95) normal (0, 0, 1) x (1, 0, 0) in component "05 Fixed end glue pedestal"
  line L0 (-5, -12) -> (5, -12)
  line L1 (5, -12) -> (5, 12)
  line L2 (5, 12) -> (-5, 12)
  line L3 (-5, 12) -> (-5, -12)
extrude "END ONLY 10x24 glue landing" add sketch "END ONLY 10x24 glue landing sketch" along normal blind 1.25 bodies 5 in component "05 Fixed end glue pedestal"
ref_plane "WorkPlane2" through (0, 0, 20.7) normal (0, 0, 1) x (1, 0, 0) in component "05 Fixed end glue pedestal"
sketch "Shallow glue key groove -3 sketch" plane through (0, 0, 20.7) normal (0, 0, 1) x (1, 0, 0) in component "05 Fixed end glue pedestal"
  line L0 (-3.4, -10) -> (-2.6, -10)
  line L1 (-2.6, -10) -> (-2.6, 10)
  line L2 (-2.6, 10) -> (-3.4, 10)
  line L3 (-3.4, 10) -> (-3.4, -10)
extrude "Shallow glue key groove -3" cut sketch "Shallow glue key groove -3 sketch" along normal blind 0.6 bodies 5 in component "05 Fixed end glue pedestal"
ref_plane "WorkPlane3" through (0, 0, 20.7) normal (0, 0, 1) x (1, 0, 0) in component "05 Fixed end glue pedestal"
sketch "Shallow glue key groove 0 sketch" plane through (0, 0, 20.7) normal (0, 0, 1) x (1, 0, 0) in component "05 Fixed end glue pedestal"
  line L0 (-0.4, -10) -> (0.4, -10)
  line L1 (0.4, -10) -> (0.4, 10)
  line L2 (0.4, 10) -> (-0.4, 10)
  line L3 (-0.4, 10) -> (-0.4, -10)
extrude "Shallow glue key groove 0" cut sketch "Shallow glue key groove 0 sketch" along normal blind 0.6 bodies 5 in component "05 Fixed end glue pedestal"
ref_plane "WorkPlane4" through (0, 0, 20.7) normal (0, 0, 1) x (1, 0, 0) in component "05 Fixed end glue pedestal"
sketch "Shallow glue key groove 3 sketch" plane through (0, 0, 20.7) normal (0, 0, 1) x (1, 0, 0) in component "05 Fixed end glue pedestal"
  line L0 (2.6, -10) -> (3.4, -10)
  line L1 (3.4, -10) -> (3.4, 10)
  line L2 (3.4, 10) -> (2.6, 10)
  line L3 (2.6, 10) -> (2.6, -10)
extrude "Shallow glue key groove 3" cut sketch "Shallow glue key groove 3 sketch" along normal blind 0.6 bodies 5 in component "05 Fixed end glue pedestal"
ref_plane "WorkPlane5" through (0, 0, -0.05) normal (0, 0, 1) x (1, 0, 0) in component "05 Fixed end glue pedestal"
sketch "Optional tie return slot -13.5 sketch" plane through (0, 0, -0.05) normal (0, 0, 1) x (1, 0, 0) in component "05 Fixed end glue pedestal"
  arc A0 (-1, -12.3) -> (-1, -14.7) centre (-1, -13.5) ccw
  line L0 (-1, -12.3) -> (1, -12.3)
  arc A1 (1, -14.7) -> (1, -12.3) centre (1, -13.5) ccw
  line L1 (1, -14.7) -> (-1, -14.7)
extrude "Optional tie return slot -13.5" cut sketch "Optional tie return slot -13.5 sketch" along normal blind 20.1 bodies 5 in component "05 Fixed end glue pedestal"
ref_plane "WorkPlane6" through (0, 0, -0.05) normal (0, 0, 1) x (1, 0, 0) in component "05 Fixed end glue pedestal"
sketch "Optional tie return slot 13.5 sketch" plane through (0, 0, -0.05) normal (0, 0, 1) x (1, 0, 0) in component "05 Fixed end glue pedestal"
  arc A0 (-1, 14.7) -> (-1, 12.3) centre (-1, 13.5) ccw
  line L0 (-1, 14.7) -> (1, 14.7)
  arc A1 (1, 12.3) -> (1, 14.7) centre (1, 13.5) ccw
  line L1 (1, 12.3) -> (-1, 12.3)
extrude "Optional tie return slot 13.5" cut sketch "Optional tie return slot 13.5 sketch" along normal blind 20.1 bodies 5 in component "05 Fixed end glue pedestal"
ref_plane "WorkPlane7" through (0, 0, -0.05) normal (0, 0, 1) x (1, 0, 0) in component "05 Fixed end glue pedestal"
sketch "Pedestal rail bolt -9 -11 sketch" plane through (0, 0, -0.05) normal (0, 0, 1) x (1, 0, 0) in component "05 Fixed end glue pedestal"
  circle A0 centre (-9, -11) radius 1.7
  dimension "d295" = 3.4
  measures "d295" diameter of A0
extrude "Pedestal rail bolt -9 -11" cut sketch "Pedestal rail bolt -9 -11 sketch" along normal blind 20.1 bodies 5 in component "05 Fixed end glue pedestal"
ref_plane "WorkPlane8" through (0, 0, -0.05) normal (0, 0, 1) x (1, 0, 0) in component "05 Fixed end glue pedestal"
sketch "Pedestal rail bolt -9 11 sketch" plane through (0, 0, -0.05) normal (0, 0, 1) x (1, 0, 0) in component "05 Fixed end glue pedestal"
  circle A0 centre (-9, 11) radius 1.7
  dimension "d300" = 3.4
  measures "d300" diameter of A0
extrude "Pedestal rail bolt -9 11" cut sketch "Pedestal rail bolt -9 11 sketch" along normal blind 20.1 bodies 5 in component "05 Fixed end glue pedestal"
ref_plane "WorkPlane9" through (0, 0, -0.05) normal (0, 0, 1) x (1, 0, 0) in component "05 Fixed end glue pedestal"
sketch "Pedestal rail bolt 9 -11 sketch" plane through (0, 0, -0.05) normal (0, 0, 1) x (1, 0, 0) in component "05 Fixed end glue pedestal"
  circle A0 centre (9, -11) radius 1.7
  dimension "d305" = 3.4
  measures "d305" diameter of A0
extrude "Pedestal rail bolt 9 -11" cut sketch "Pedestal rail bolt 9 -11 sketch" along normal blind 20.1 bodies 5 in component "05 Fixed end glue pedestal"
ref_plane "WorkPlane10" through (0, 0, -0.05) normal (0, 0, 1) x (1, 0, 0) in component "05 Fixed end glue pedestal"
sketch "Pedestal rail bolt 9 11 sketch" plane through (0, 0, -0.05) normal (0, 0, 1) x (1, 0, 0) in component "05 Fixed end glue pedestal"
  circle A0 centre (9, 11) radius 1.7
  dimension "d310" = 3.4
  measures "d310" diameter of A0
extrude "Pedestal rail bolt 9 11" cut sketch "Pedestal rail bolt 9 11 sketch" along normal blind 20.1 bodies 5 in component "05 Fixed end glue pedestal"
sketch "Glue carrier body sketch (2)" plane through (0, 0, 0) normal (0, 0, 1) x (1, 0, 0) in component "06 Free end glue hanger"
  line L0 (-13, -17) -> (13, -17)
  line L1 (13, -17) -> (13, 17)
  line L2 (13, 17) -> (-13, 17)
  line L3 (-13, 17) -> (-13, -17)
extrude "Glue carrier body'" add sketch "Glue carrier body sketch (2)" along normal blind 10 separate body makes body 6 in component "06 Free end glue hanger"
ref_plane "WorkPlane1" through (0, 0, 9.95) normal (0, 0, 1) x (1, 0, 0) in component "06 Free end glue hanger"
sketch "END ONLY 10x24 glue landing sketch (2)" plane through (0, 0, 9.95) normal (0, 0, 1) x (1, 0, 0) in component "06 Free end glue hanger"
  line L0 (-5, -12) -> (5, -12)
  line L1 (5, -12) -> (5, 12)
  line L2 (5, 12) -> (-5, 12)
  line L3 (-5, 12) -> (-5, -12)
extrude "END ONLY 10x24 glue landing'" add sketch "END ONLY 10x24 glue landing sketch (2)" along normal blind 1.25 bodies 6 in component "06 Free end glue hanger"
ref_plane "WorkPlane2" through (0, 0, 10.7) normal (0, 0, 1) x (1, 0, 0) in component "06 Free end glue hanger"
sketch "Shallow glue key groove -3 sketch (2)" plane through (0, 0, 10.7) normal (0, 0, 1) x (1, 0, 0) in component "06 Free end glue hanger"
  line L0 (-3.4, -10) -> (-2.6, -10)
  line L1 (-2.6, -10) -> (-2.6, 10)
  line L2 (-2.6, 10) -> (-3.4, 10)
  line L3 (-3.4, 10) -> (-3.4, -10)
extrude "Shallow glue key groove -3'" cut sketch "Shallow glue key groove -3 sketch (2)" along normal blind 0.6 bodies 6 in component "06 Free end glue hanger"
ref_plane "WorkPlane3" through (0, 0, 10.7) normal (0, 0, 1) x (1, 0, 0) in component "06 Free end glue hanger"
sketch "Shallow glue key groove 0 sketch (2)" plane through (0, 0, 10.7) normal (0, 0, 1) x (1, 0, 0) in component "06 Free end glue hanger"
  line L0 (-0.4, -10) -> (0.4, -10)
  line L1 (0.4, -10) -> (0.4, 10)
  line L2 (0.4, 10) -> (-0.4, 10)
  line L3 (-0.4, 10) -> (-0.4, -10)
extrude "Shallow glue key groove 0'" cut sketch "Shallow glue key groove 0 sketch (2)" along normal blind 0.6 bodies 6 in component "06 Free end glue hanger"
ref_plane "WorkPlane4" through (0, 0, 10.7) normal (0, 0, 1) x (1, 0, 0) in component "06 Free end glue hanger"
sketch "Shallow glue key groove 3 sketch (2)" plane through (0, 0, 10.7) normal (0, 0, 1) x (1, 0, 0) in component "06 Free end glue hanger"
  line L0 (2.6, -10) -> (3.4, -10)
  line L1 (3.4, -10) -> (3.4, 10)
  line L2 (3.4, 10) -> (2.6, 10)
  line L3 (2.6, 10) -> (2.6, -10)
extrude "Shallow glue key groove 3'" cut sketch "Shallow glue key groove 3 sketch (2)" along normal blind 0.6 bodies 6 in component "06 Free end glue hanger"
ref_plane "WorkPlane5" through (0, 0, -0.05) normal (0, 0, 1) x (1, 0, 0) in component "06 Free end glue hanger"
sketch "Optional tie return slot -13.5 sketch (2)" plane through (0, 0, -0.05) normal (0, 0, 1) x (1, 0, 0) in component "06 Free end glue hanger"
  arc A0 (-1, -12.3) -> (-1, -14.7) centre (-1, -13.5) ccw
  line L0 (-1, -12.3) -> (1, -12.3)
  arc A1 (1, -14.7) -> (1, -12.3) centre (1, -13.5) ccw
  line L1 (1, -14.7) -> (-1, -14.7)
extrude "Optional tie return slot -13.5'" cut sketch "Optional tie return slot -13.5 sketch (2)" along normal blind 10.1 bodies 6 in component "06 Free end glue hanger"
ref_plane "WorkPlane6" through (0, 0, -0.05) normal (0, 0, 1) x (1, 0, 0) in component "06 Free end glue hanger"
sketch "Optional tie return slot 13.5 sketch (2)" plane through (0, 0, -0.05) normal (0, 0, 1) x (1, 0, 0) in component "06 Free end glue hanger"
  arc A0 (-1, 14.7) -> (-1, 12.3) centre (-1, 13.5) ccw
  line L0 (-1, 14.7) -> (1, 14.7)
  arc A1 (1, 12.3) -> (1, 14.7) centre (1, 13.5) ccw
  line L1 (1, 12.3) -> (-1, 12.3)
extrude "Optional tie return slot 13.5'" cut sketch "Optional tie return slot 13.5 sketch (2)" along normal blind 10.1 bodies 6 in component "06 Free end glue hanger"
sketch "Transverse cord hole sketch" plane through (0, 0, 0) normal (0, 1, 0) x (1, 0, 0) in component "06 Free end glue hanger"
  circle A0 centre (0, -5) radius 1.75
extrude "Transverse cord hole" cut sketch "Transverse cord hole sketch" along normal mid plane 34.1 bodies 6 in component "06 Free end glue hanger"
sketch "Fit block sketch" plane through (0, 0, 0) normal (0, 0, 1) x (1, 0, 0) in component "07 Spar fit coupon - 4.1 4.3 4.4 4.5 4.7"
  line L0 (0, 0) -> (24, 0)
  line L1 (24, 0) -> (24, 60)
  line L2 (24, 60) -> (0, 60)
  line L3 (0, 60) -> (0, 0)
extrude "Fit block" add sketch "Fit block sketch" along normal blind 8 separate body makes body 7 in component "07 Spar fit coupon - 4.1 4.3 4.4 4.5 4.7"
ref_plane "WorkPlane1" through (-0.05, 0, 0) normal (1, 0, 0) x (0, 1, 0) in component "07 Spar fit coupon - 4.1 4.3 4.4 4.5 4.7"
sketch "Horizontal 4.1 mm fit bore sketch" plane through (-0.05, 0, 0) normal (1, 0, 0) x (0, 0, -1) in component "07 Spar fit coupon - 4.1 4.3 4.4 4.5 4.7"
  circle A0 centre (-3.5, 6) radius 2.05
extrude "Horizontal 4.1 mm fit bore" cut sketch "Horizontal 4.1 mm fit bore sketch" along normal blind 24.1 bodies 7 in component "07 Spar fit coupon - 4.1 4.3 4.4 4.5 4.7"
ref_plane "WorkPlane2" through (0, 0, 7.4) normal (0, 0, 1) x (1, 0, 0) in component "07 Spar fit coupon - 4.1 4.3 4.4 4.5 4.7"
sketch "Label 4.1 digit 0 f sketch" plane through (0, 0, 7.4) normal (0, 0, 1) x (1, 0, 0) in component "07 Spar fit coupon - 4.1 4.3 4.4 4.5 4.7"
  line L0 (8, 6.15) -> (8.3, 6.15)
  line L1 (8.3, 6.15) -> (8.3, 7.05)
  line L2 (8.3, 7.05) -> (8, 7.05)
  line L3 (8, 7.05) -> (8, 6.15)
extrude "Label 4.1 digit 0 f" cut sketch "Label 4.1 digit 0 f sketch" along normal blind 1 bodies 7 in component "07 Spar fit coupon - 4.1 4.3 4.4 4.5 4.7"
ref_plane "WorkPlane3" through (0, 0, 7.4) normal (0, 0, 1) x (1, 0, 0) in component "07 Spar fit coupon - 4.1 4.3 4.4 4.5 4.7"
sketch "Label 4.1 digit 0 g sketch" plane through (0, 0, 7.4) normal (0, 0, 1) x (1, 0, 0) in component "07 Spar fit coupon - 4.1 4.3 4.4 4.5 4.7"
  line L0 (8, 5.85) -> (9.8, 5.85)
  line L1 (9.8, 5.85) -> (9.8, 6.15)
  line L2 (9.8, 6.15) -> (8, 6.15)
  line L3 (8, 6.15) -> (8, 5.85)
extrude "Label 4.1 digit 0 g" cut sketch "Label 4.1 digit 0 g sketch" along normal blind 1 bodies 7 in component "07 Spar fit coupon - 4.1 4.3 4.4 4.5 4.7"
ref_plane "WorkPlane4" through (0, 0, 7.4) normal (0, 0, 1) x (1, 0, 0) in component "07 Spar fit coupon - 4.1 4.3 4.4 4.5 4.7"
sketch "Label 4.1 digit 0 b sketch" plane through (0, 0, 7.4) normal (0, 0, 1) x (1, 0, 0) in component "07 Spar fit coupon - 4.1 4.3 4.4 4.5 4.7"
  line L0 (9.5, 6.15) -> (9.8, 6.15)
  line L1 (9.8, 6.15) -> (9.8, 7.05)
  line L2 (9.8, 7.05) -> (9.5, 7.05)
  line L3 (9.5, 7.05) -> (9.5, 6.15)
extrude "Label 4.1 digit 0 b" cut sketch "Label 4.1 digit 0 b sketch" along normal blind 1 bodies 7 in component "07 Spar fit coupon - 4.1 4.3 4.4 4.5 4.7"